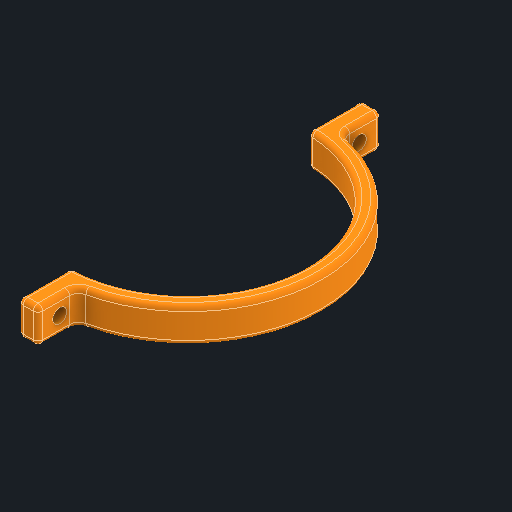
# Autodesk Inventor part: dec_clamp_cap
Saved by Autodesk Inventor 2027.1 (Build 311270010, 270A)
## iProperties
Created: 2026-11-04
Part Number: dec_clamp_cap
Material: Generic
Description: Dec clamp cap: other half of ring 1 round the Dec housing, 2 M4 bolts (+Z M4x25, -Z M4x16) into M4 nuts in the bracket
Document SubType Name: Modeling
Designer: Claude (from photos)
Density: 1 g/cm^3
Appearance: Orange
Author: alexg
Autodesk Inventor part; units mm, degrees
ref_plane "Work Plane1" through (0, 47, 0) normal (0, 1, 0) x (-1, 0, 0)
sketch "Clamp ring sketch" plane through (0, 47, 0) normal (0, 1, 0) x (-1, 0, 0)
  circle A0 centre (-187, 0) radius 43
  circle A1 centre (-187, 0) radius 38
  constraints: 2 centre point
extrude "Clamp ring" add sketch "Clamp ring sketch" along normal blind 11
ref_plane "Work Plane2" through (0, 47, 0) normal (0, 1, 0) x (-1, 0, 0)
sketch "Keep the far half sketch" plane through (0, 47, 0) normal (0, 1, 0) x (-1, 0, 0)
  line L0 (-127, -60) -> (-187.75, -60)
  line L1 (-187.75, -60) -> (-187.75, 60)
  line L2 (-187.75, 60) -> (-127, 60)
  line L3 (-127, 60) -> (-127, -60)
  constraints: 8 end point, 2 parallel, 1 horizontal, 1 perpendicular
extrude "Keep the far half" cut sketch "Keep the far half sketch" along normal blind 11
ref_plane "Work Plane3" through (0, 47, 0) normal (0, 1, 0) x (-1, 0, 0)
sketch "Clamp ears sketch" plane through (0, 47, 0) normal (0, 1, 0) x (-1, 0, 0)
  line L0 (-187.75, 41) -> (-194, 41)
  line L1 (-194, 41) -> (-194, 55)
  line L2 (-194, 55) -> (-187.75, 55)
  line L3 (-187.75, 55) -> (-187.75, 41)
  line L4 (-187.75, -55) -> (-194, -55)
  line L5 (-194, -55) -> (-194, -41)
  line L6 (-194, -41) -> (-187.75, -41)
  line L7 (-187.75, -41) -> (-187.75, -55)
  constraints: 16 end point, 4 parallel, 2 horizontal, 2 perpendicular
extrude "Clamp ears" add sketch "Clamp ears sketch" along normal blind 11
ref_plane "Work Plane4" through (187.75, 0, 0) normal (1, 0, 0) x (0, 1, 0)
sketch "M4 clearance holes sketch" plane through (187.75, 0, 0) normal (1, 0, 0) x (0, 1, 0)
  circle A0 centre (52.5, 48) radius 2.25
  circle A1 centre (52.5, -48) radius 2.25
  constraints: 2 centre point
extrude "M4 clearance holes" cut sketch "M4 clearance holes sketch" along normal blind 10
fillet "Fillets (inside corners) R3 (2 edges)" radius 3 2 edges at (194, 52.5, 42.4264) (194, 52.5, -42.4264)
fillet "Rounds (outside edges) R1.5 (22 edges)" radius 1.5 22 edges at (194, 58, 49.9499) (194, 52.5, 55) (194, 47, 49.9499) (190.875, 47, 55) (190.875, 58, 55) (187.75, 52.5, 55) (194, 47, -49.9499) (194, 52.5, -55) (194, 58, -49.9499) (190.875, 47, -55) (187.75, 52.5, -55) (190.875, 58, -55) (230, 47, 0) (230, 58, 0) (187.75, 47, 46.4963) (225, 47, 0) (187.75, 47, -46.4963) (187.75, 58, 46.4963) (187.75, 52.5, 37.9926) (187.75, 52.5, -37.9926) (187.75, 58, -46.4963) (225, 58, 0)
body "Solid1"
